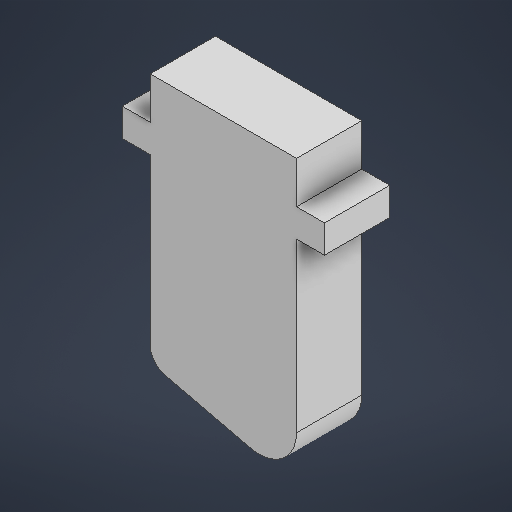
# Autodesk Inventor part: 6_10_piece_mobile_detection3
Saved by Autodesk Inventor 2026 (Build 300175000, 175)
## iProperties
Created: 2025-06-19
Part Number: 6_10_piece_mobile_detection3
Material: Générique
Document SubType Name: Modeling
Designer: Diogo
Density: 1 g/cm^3
Appearance: Par défaut
Author: Diogo
Autodesk Inventor part; units mm, degrees
ref_plane "YZ Plane" through (0, 0, 0) normal (1, 0, 0) x (0, 1, 0)
ref_plane "XZ Plane" through (0, 0, 0) normal (0, 1, 0) x (-1, 0, 0)
ref_plane "XY Plane" through (0, 0, 0) normal (0, 0, 1) x (1, 0, 0)
sketch "Esquisse1" plane through (0, 0, 0) normal (0, 0, 1) x (1, 0, 0)
  line L0 (0, 0) -> (15.7, 0)
  arc A0 (10.7146, -29.3767) -> (15.7, -25.5) centre (11.7, -25.5) ccw
  line L1 (10.7432, -29.3838) -> (0, -26.8205)
  line L2 (15.7, 0) -> (15.7, -4.5)
  line L3 (15.7, -4.5) -> (18.7, -4.5)
  line L4 (18.7, -4.5) -> (18.7, -7.5)
  line L5 (0, 0) -> (0, -4.5)
  line L6 (0, -4.5) -> (-3, -4.5)
  line L7 (-3, -4.5) -> (-3, -7.5)
  line L8 (-3, -7.5) -> (0, -7.5)
  line L9 (0, -7.5) -> (0, -26.8205)
  line L10 (18.7, -7.5) -> (15.7, -7.5)
  line L11 (15.7, -7.5) -> (15.7, -25.5)
  point P0 (15.7, -25.5)
  point P1 (10.7313, -29.3809)
  dimension "d0" = 15.7
  dimension "d2" = 4
  dimension "d10" = 4.5
  dimension "d14" = 25.5
  dimension "d15" = 3
  dimension "d16" = 3
  dimension "d17" = 3
  constraints: 24 end point, 5 perpendicular, 3 horizontal, 3 vertical, 2 point on circle, 1 centre point, 1 point on line
  measures "d0" distance of L0.start L0.end
  measures "d2" radius of A0
  measures "d10" distance of L0.end L2.end
  measures "d14" distance from line of L0 A0.centre
  measures "d15" distance of L2.end L3.end
  measures "d16" distance of L3.end L4.end
  measures "d17" distance of L5.end L6.end
extrude "Extrusion1" add sketch "Esquisse1" along normal blind 7
fillet "Congé1" radius 2 1 edges at (0, -26.8205, 3.5)
